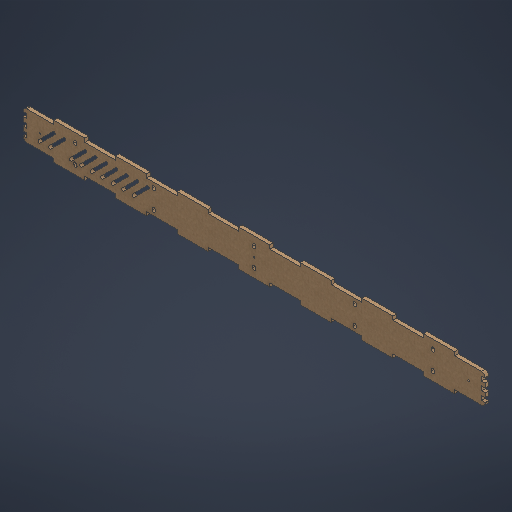
# Autodesk Inventor part: BaseBoxLengthFace
Saved by Autodesk Inventor 2027.1 (Build 311270010, 270A)
## iProperties
Created: 2026-10-13
Part Number: BaseBoxLengthFace
Material: MDF Medium Density Fiberboard
Document SubType Name: Modeling
Designer: SDS Scholar
Density: 0.8 g/cm^3
Appearance: Cardboard - Corrugated
Author: SDS Scholar
Autodesk Inventor part; units mm, degrees
ref_plane "YZ Plane" through (0, 0, 0) normal (1, 0, 0) x (0, 1, 0)
ref_plane "XZ Plane" through (0, 0, 0) normal (0, 1, 0) x (-1, 0, 0)
ref_plane "XY Plane" through (0, 0, 0) normal (0, 0, 1) x (1, 0, 0)
sketch "Sketch1" plane through (0, 0, 0) normal (0, 0, 1) x (1, 0, 0)
  line L0 (-442.5, 35) -> (442.5, 35)
  line L1 (442.5, 35) -> (442.5, -35)
  line L2 (442.5, -35) -> (-442.5, -35)
  line L3 (-442.5, -35) -> (-442.5, 35)
  point P0 (0, 0)
  point P1 (0, 35)
  point P2 (442.5, 0)
  dimension "d0" = 885
  dimension "d1" = 70
  constraints: 8 end point, 2 midpoint, 2 parallel, 1 horizontal, 1 horizontal alignment, 1 perpendicular, 1 vertical alignment
  measures "d0" distance of L0.start L0.end
  measures "d1" distance of L2.end L0.start
extrude "Extrusion1" add sketch "Sketch1" along normal blind 7
sketch "Sketch2" plane through (0, 0, 7) normal (0, 0, 1) x (1, 0, 0)
  line L0 (-383.3579, 14.1421) -> (-411.6421, -14.1421) construction
  line L1 (-385.1256, 15.9099) -> (-413.4099, -12.3744)
  line L2 (-409.8744, -15.9099) -> (-381.5901, 12.3744)
  arc A0 (-381.5901, 12.3744) -> (-385.1256, 15.9099) centre (-383.3579, 14.1421) ccw
  arc A1 (-413.4099, -12.3744) -> (-409.8744, -15.9099) centre (-411.6421, -14.1421) ccw
  line L3 (-397.5, 0) -> (-442.5, 0)
  line L4 (-442.5, 35) -> (-442.5, -35) projected
  point P0 (0, 0)
  dimension "d4" = 40
  dimension "d5" = 45
  dimension "d6" = 135
  dimension "d7" = 2.5
  constraints: 10 end point, 4 point on circle, 4 tangent, 2 centre point, 2 midpoint, 1 horizontal, 1 parallel
  measures "d4" distance of L0.start L0.end
  measures "d5" distance of L3.start L3.end
  measures "d6" angle of L3 L0
  measures "d7" radius of A1
extrude "Extrusion2" cut sketch "Sketch2" against normal through all
pattern_linear "Rectangular Pattern1" count 10 spacing 20 along (1, 0, 0) of "Extrusion2"
sketch "Sketch3" plane through (0, 0, 0) normal (0, 0, -1) x (-1, 0, 0)
  arc A0 (205.1256, 15.9099) -> (201.5901, 12.3744) centre (203.3579, 14.1421) ccw projected
  line L0 (205.1256, 15.9099) -> (233.4099, -12.3744) projected
  arc A1 (229.8744, -15.9099) -> (233.4099, -12.3744) centre (231.6421, -14.1421) ccw projected
  line L1 (229.8744, -15.9099) -> (201.5901, 12.3744) projected
  arc A2 (225.1256, 15.9099) -> (221.5901, 12.3744) centre (223.3579, 14.1421) ccw projected
  line L2 (225.1256, 15.9099) -> (253.4099, -12.3744) projected
  arc A3 (249.8744, -15.9099) -> (253.4099, -12.3744) centre (251.6421, -14.1421) ccw projected
  line L3 (249.8744, -15.9099) -> (221.5901, 12.3744) projected
  arc A4 (245.1256, 15.9099) -> (241.5901, 12.3744) centre (243.3579, 14.1421) ccw projected
  line L4 (245.1256, 15.9099) -> (273.4099, -12.3744) projected
  arc A5 (269.8744, -15.9099) -> (273.4099, -12.3744) centre (271.6421, -14.1421) ccw projected
  line L5 (269.8744, -15.9099) -> (241.5901, 12.3744) projected
  arc A6 (265.1256, 15.9099) -> (261.5901, 12.3744) centre (263.3579, 14.1421) ccw projected
  line L6 (265.1256, 15.9099) -> (293.4099, -12.3744) projected
  arc A7 (289.8744, -15.9099) -> (293.4099, -12.3744) centre (291.6421, -14.1421) ccw projected
  line L7 (289.8744, -15.9099) -> (261.5901, 12.3744) projected
  arc A8 (285.1256, 15.9099) -> (281.5901, 12.3744) centre (283.3579, 14.1421) ccw projected
  line L8 (285.1256, 15.9099) -> (313.4099, -12.3744) projected
  arc A9 (309.8744, -15.9099) -> (313.4099, -12.3744) centre (311.6421, -14.1421) ccw projected
  line L9 (309.8744, -15.9099) -> (281.5901, 12.3744) projected
  arc A10 (305.1256, 15.9099) -> (301.5901, 12.3744) centre (303.3579, 14.1421) ccw projected
  line L10 (305.1256, 15.9099) -> (333.4099, -12.3744) projected
  arc A11 (329.8744, -15.9099) -> (333.4099, -12.3744) centre (331.6421, -14.1421) ccw projected
  line L11 (329.8744, -15.9099) -> (301.5901, 12.3744) projected
  arc A12 (325.1256, 15.9099) -> (321.5901, 12.3744) centre (323.3579, 14.1421) ccw projected
  line L12 (325.1256, 15.9099) -> (353.4099, -12.3744) projected
  arc A13 (349.8744, -15.9099) -> (353.4099, -12.3744) centre (351.6421, -14.1421) ccw projected
  line L13 (349.8744, -15.9099) -> (321.5901, 12.3744) projected
  arc A14 (345.1256, 15.9099) -> (341.5901, 12.3744) centre (343.3579, 14.1421) ccw projected
  line L14 (345.1256, 15.9099) -> (373.4099, -12.3744) projected
  arc A15 (369.8744, -15.9099) -> (373.4099, -12.3744) centre (371.6421, -14.1421) ccw projected
  line L15 (369.8744, -15.9099) -> (341.5901, 12.3744) projected
  arc A16 (365.1256, 15.9099) -> (361.5901, 12.3744) centre (363.3579, 14.1421) ccw projected
  line L16 (365.1256, 15.9099) -> (393.4099, -12.3744) projected
  arc A17 (389.8744, -15.9099) -> (393.4099, -12.3744) centre (391.6421, -14.1421) ccw projected
  line L17 (389.8744, -15.9099) -> (361.5901, 12.3744) projected
  arc A18 (409.8744, -15.9099) -> (413.4099, -12.3744) centre (411.6421, -14.1421) ccw projected
  line L18 (409.8744, -15.9099) -> (381.5901, 12.3744) projected
  arc A19 (385.1256, 15.9099) -> (381.5901, 12.3744) centre (383.3579, 14.1421) ccw projected
  line L19 (385.1256, 15.9099) -> (413.4099, -12.3744) projected
  line L20 (442.5, -35) -> (-442.5, -35) projected
  line L21 (442.5, 35) -> (442.5, -35) projected
  line L22 (-442.5, 35) -> (442.5, 35) projected
  line L23 (-442.5, -35) -> (-442.5, 35) projected
  line L24 (435.5, 28) -> (435.5, -28)
  line L25 (435.5, -28) -> (-435.5, -28)
  line L26 (-435.5, -28) -> (-435.5, 28)
  line L27 (-435.5, 28) -> (435.5, 28)
  line L28 (-442.5, 35) -> (-383.725, 35)
  line L29 (-383.725, 35) -> (-383.725, 28)
  line L30 (-383.725, 28) -> (-442.5, 28)
  line L31 (-442.5, 28) -> (-442.5, 35)
  line L32 (-383.725, 35) -> (-324.275, 35)
  line L33 (-324.275, 35) -> (-324.275, 28)
  line L34 (-324.275, 28) -> (-383.725, 28)
  line L35 (-383.725, 28) -> (-383.725, 35)
  line L36 (-265.725, 35) -> (-265.725, 28)
  line L37 (-206.275, 35) -> (-206.275, 28)
  line L38 (-147.725, 35) -> (-147.725, 28)
  line L39 (-88.275, 35) -> (-88.275, 28)
  line L40 (-29.725, 35) -> (-29.725, 28)
  line L41 (29.725, 35) -> (29.725, 28)
  line L42 (88.275, 35) -> (88.275, 28)
  line L43 (147.725, 35) -> (147.725, 28)
  line L44 (206.275, 35) -> (206.275, 28)
  line L45 (265.725, 35) -> (265.725, 28)
  line L46 (324.275, 35) -> (324.275, 28)
  line L47 (383.725, 35) -> (383.725, 28)
  line L48 (0, 35) -> (0, -35) construction
  line L49 (-442.5, 0) -> (442.5, 0) construction
  line L50 (-383.725, -35) -> (-383.725, -28)
  line L51 (-324.275, -35) -> (-324.275, -28)
  line L52 (-265.725, -35) -> (-265.725, -28)
  line L53 (-206.275, -35) -> (-206.275, -28)
  line L54 (-147.725, -35) -> (-147.725, -28)
  line L55 (-88.275, -35) -> (-88.275, -28)
  line L56 (-29.725, -35) -> (-29.725, -28)
  line L57 (29.725, -35) -> (29.725, -28)
  line L58 (88.275, -35) -> (88.275, -28)
  line L59 (147.725, -35) -> (147.725, -28)
  line L60 (206.275, -35) -> (206.275, -28)
  line L61 (265.725, -35) -> (265.725, -28)
  line L62 (324.275, -35) -> (324.275, -28)
  line L63 (383.725, -35) -> (383.725, -28)
  line L64 (-442.5, 28) -> (-435.5, 28)
  line L65 (-435.5, 28) -> (-435.5, 20)
  line L66 (-435.5, 20) -> (-442.5, 20)
  line L67 (-442.5, 20) -> (-442.5, 28)
  line L68 (-442.5, 20) -> (-435.5, 20)
  line L69 (-435.5, 20) -> (-435.5, 12)
  line L70 (-435.5, 12) -> (-442.5, 12)
  line L71 (-442.5, 12) -> (-442.5, 20)
  line L72 (-442.5, 4) -> (-435.5, 4)
  line L73 (-435.5, -4) -> (-442.5, -4)
  line L74 (-442.5, 12) -> (-435.5, 12)
  line L75 (-442.5, -12) -> (-435.5, -12)
  line L76 (-435.5, -20) -> (-442.5, -20)
  line L77 (-442.5, -4) -> (-435.5, -4)
  line L78 (-435.5, -28) -> (-442.5, -28)
  line L79 (383.725, 28) -> (442.5, 28)
  line L80 (435.5, 20) -> (442.5, 20)
  line L81 (442.5, 4) -> (435.5, 4)
  line L82 (435.5, -4) -> (442.5, -4)
  line L83 (442.5, 12) -> (435.5, 12)
  line L84 (442.5, -12) -> (435.5, -12)
  line L85 (435.5, -20) -> (442.5, -20)
  line L86 (435.5, -28) -> (442.5, -28)
  point P0 (0, 0)
  point P1 (383.725, -28)
  point P2 (383.725, -35)
  point P3 (265.725, -28)
  point P4 (265.725, -35)
  point P5 (324.275, -35)
  point P6 (324.275, -28)
  point P7 (147.725, -28)
  point P8 (147.725, -35)
  point P9 (206.275, -35)
  point P10 (206.275, -28)
  point P11 (29.725, -28)
  point P12 (29.725, -35)
  point P13 (88.275, -35)
  point P14 (88.275, -28)
  point P15 (-88.275, -28)
  point P16 (-88.275, -35)
  point P17 (-29.725, -35)
  point P18 (-29.725, -28)
  point P19 (-206.275, -28)
  point P20 (-206.275, -35)
  point P21 (-147.725, -35)
  point P22 (-147.725, -28)
  point P23 (-324.275, -28)
  point P24 (-324.275, -35)
  point P25 (-265.725, -35)
  point P26 (-265.725, -28)
  point P27 (-383.725, -35)
  point P28 (-383.725, -28)
  point P29 (383.725, 28)
  point P30 (324.275, 28)
  point P31 (265.725, 28)
  point P32 (206.275, 28)
  point P33 (147.725, 28)
  point P34 (88.275, 28)
  point P35 (29.725, 28)
  point P36 (-29.725, 28)
  point P37 (-88.275, 28)
  point P38 (-147.725, 28)
  point P39 (-206.275, 28)
  point P40 (-265.725, 28)
  point P41 (435.5, 28)
  point P42 (435.5, 28)
  point P43 (-435.5, 28)
  dimension "d13" = 7
  dimension "d14" = 58.775
  dimension "d15" = 59.45
  dimension "d18" = 118
  dimension "d23" = 8
  dimension "d24" = 8
  dimension "d27" = 16
  constraints: 126 end point, 43 symmetric about line, 8 parallel, 5 horizontal, 5 perpendicular, 5 point on line, 4 midpoint, 1 vertical, 57 other
  measures "d13" distance between parallel lines of L22 L27
  measures "d14" distance between parallel lines of L23 L29
  measures "d15" distance between parallel lines of L33 L29
  measures "d18" distance of L28.end L36.start
  measures "d23" distance between parallel lines of L30 L66
  measures "d24" distance between parallel lines of L70 L66
  measures "d27" distance of L66.end L72.start
extrude "Extrusion3" cut sketch "Sketch3" against normal through all contours L20 L63 L25 L86 L21 | L20 L61 L25 L62 | L85 L24 L84 L21 | L20 L59 L25 L60 | L82 L24 L81 L21 | L20 L57 L25 L58 | L83 L24 L80 L21 | L20 L55 L25 L56 | L79 L27 L47 L22 L21 | L20 L53 L25 L54 | L46 L27 L45 L22 | L20 L51 L25 L52 | L44 L27 L43 L22 | L20 L23 L78 L25 L50 | L42 L27 L41 L22 | L23 L75 L26 L76 | L40 L27 L39 L22 | L23 L72 L26 L73 | L38 L27 L37 L22 | L23 L66 L26 L70 | L36 L27 L33 L22 | L23 L22 L29 L27 L30
fillet "Fillet2" radius 7 4 edges at (442.5, 28, 3.5) (442.5, -28, 3.5) (-442.5, 28, 3.5) (-442.5, -28, 3.5)
sketch "Sketch4" plane through (0, 0, 7) normal (0, 0, 1) x (1, 0, 0)
  arc A0 (-442.5, -21) -> (-435.5, -28) centre (-435.5, -21) ccw projected
  line L0 (-435.5, -28) -> (-383.725, -28) projected
  line L1 (-383.725, -28) -> (-383.725, -35) projected
  line L2 (-383.725, -35) -> (-324.275, -35) projected
  line L3 (-324.275, -35) -> (-324.275, -28) projected
  line L4 (-324.275, -28) -> (-265.725, -28) projected
  line L5 (-265.725, -28) -> (-265.725, -35) projected
  line L6 (-265.725, -35) -> (-206.275, -35) projected
  line L7 (-206.275, -35) -> (-206.275, -28) projected
  line L8 (-206.275, -28) -> (-147.725, -28) projected
  line L9 (-147.725, -28) -> (-147.725, -35) projected
  line L10 (-147.725, -35) -> (-88.275, -35) projected
  line L11 (-88.275, -35) -> (-88.275, -28) projected
  line L12 (-88.275, -28) -> (-29.725, -28) projected
  line L13 (-29.725, -28) -> (-29.725, -35) projected
  line L14 (-29.725, -35) -> (29.725, -35) projected
  line L15 (29.725, -35) -> (29.725, -28) projected
  line L16 (29.725, -28) -> (88.275, -28) projected
  line L17 (88.275, -28) -> (88.275, -35) projected
  line L18 (88.275, -35) -> (147.725, -35) projected
  line L19 (147.725, -35) -> (147.725, -28) projected
  line L20 (147.725, -28) -> (206.275, -28) projected
  line L21 (206.275, -28) -> (206.275, -35) projected
  line L22 (206.275, -35) -> (265.725, -35) projected
  line L23 (265.725, -35) -> (265.725, -28) projected
  line L24 (265.725, -28) -> (324.275, -28) projected
  line L25 (324.275, -28) -> (324.275, -35) projected
  line L26 (324.275, -35) -> (383.725, -35) projected
  line L27 (383.725, -35) -> (383.725, -28) projected
  line L28 (383.725, -28) -> (435.5, -28) projected
  arc A1 (435.5, -28) -> (442.5, -21) centre (435.5, -21) ccw projected
  line L29 (442.5, -21) -> (442.5, -20) projected
  line L30 (442.5, -20) -> (435.5, -20) projected
  line L31 (435.5, -20) -> (435.5, -12) projected
  line L32 (435.5, -12) -> (442.5, -12) projected
  line L33 (442.5, -12) -> (442.5, -4) projected
  line L34 (442.5, -4) -> (435.5, -4) projected
  line L35 (435.5, -4) -> (435.5, 4) projected
  line L36 (435.5, 4) -> (442.5, 4) projected
  line L37 (442.5, 4) -> (442.5, 12) projected
  line L38 (442.5, 12) -> (435.5, 12) projected
  line L39 (435.5, 12) -> (435.5, 20) projected
  line L40 (435.5, 20) -> (442.5, 20) projected
  line L41 (442.5, 20) -> (442.5, 21) projected
  arc A2 (442.5, 21) -> (435.5, 28) centre (435.5, 21) ccw projected
  line L42 (435.5, 28) -> (383.725, 28) projected
  line L43 (383.725, 28) -> (383.725, 35) projected
  line L44 (383.725, 35) -> (324.275, 35) projected
  line L45 (324.275, 35) -> (324.275, 28) projected
  line L46 (324.275, 28) -> (265.725, 28) projected
  line L47 (265.725, 28) -> (265.725, 35) projected
  line L48 (265.725, 35) -> (206.275, 35) projected
  line L49 (206.275, 35) -> (206.275, 28) projected
  line L50 (206.275, 28) -> (147.725, 28) projected
  line L51 (147.725, 28) -> (147.725, 35) projected
  line L52 (147.725, 35) -> (88.275, 35) projected
  line L53 (88.275, 35) -> (88.275, 28) projected
  line L54 (88.275, 28) -> (29.725, 28) projected
  line L55 (29.725, 28) -> (29.725, 35) projected
  line L56 (29.725, 35) -> (-29.725, 35) projected
  line L57 (-29.725, 35) -> (-29.725, 28) projected
  line L58 (-29.725, 28) -> (-88.275, 28) projected
  line L59 (-88.275, 28) -> (-88.275, 35) projected
  line L60 (-88.275, 35) -> (-147.725, 35) projected
  line L61 (-147.725, 35) -> (-147.725, 28) projected
  line L62 (-147.725, 28) -> (-206.275, 28) projected
  line L63 (-206.275, 28) -> (-206.275, 35) projected
  line L64 (-206.275, 35) -> (-265.725, 35) projected
  line L65 (-265.725, 35) -> (-265.725, 28) projected
  line L66 (-265.725, 28) -> (-324.275, 28) projected
  line L67 (-324.275, 28) -> (-324.275, 35) projected
  line L68 (-324.275, 35) -> (-383.725, 35) projected
  line L69 (-383.725, 35) -> (-383.725, 28) projected
  line L70 (-383.725, 28) -> (-435.5, 28) projected
  arc A3 (-435.5, 28) -> (-442.5, 21) centre (-435.5, 21) ccw projected
  line L71 (-442.5, 21) -> (-442.5, 20) projected
  line L72 (-442.5, 20) -> (-435.5, 20) projected
  line L73 (-435.5, 20) -> (-435.5, 12) projected
  line L74 (-435.5, 12) -> (-442.5, 12) projected
  line L75 (-442.5, 12) -> (-442.5, 4) projected
  line L76 (-442.5, 4) -> (-435.5, 4) projected
  line L77 (-435.5, 4) -> (-435.5, -4) projected
  line L78 (-435.5, -4) -> (-442.5, -4) projected
  line L79 (-442.5, -4) -> (-442.5, -12) projected
  line L80 (-442.5, -12) -> (-435.5, -12) projected
  line L81 (-435.5, -12) -> (-435.5, -20) projected
  line L82 (-435.5, -20) -> (-442.5, -20) projected
  line L83 (-442.5, -20) -> (-442.5, -21) projected
  arc A4 (-413.4099, -12.3744) -> (-409.8744, -15.9099) centre (-411.6421, -14.1421) ccw projected
  line L84 (-413.4099, -12.3744) -> (-385.1256, 15.9099) projected
  arc A5 (-381.5901, 12.3744) -> (-385.1256, 15.9099) centre (-383.3579, 14.1421) ccw projected
  line L85 (-381.5901, 12.3744) -> (-409.8744, -15.9099) projected
  arc A6 (-361.5901, 12.3744) -> (-365.1256, 15.9099) centre (-363.3579, 14.1421) ccw projected
  line L86 (-361.5901, 12.3744) -> (-389.8744, -15.9099) projected
  arc A7 (-393.4099, -12.3744) -> (-389.8744, -15.9099) centre (-391.6421, -14.1421) ccw projected
  line L87 (-393.4099, -12.3744) -> (-365.1256, 15.9099) projected
  arc A8 (-341.5901, 12.3744) -> (-345.1256, 15.9099) centre (-343.3579, 14.1421) ccw projected
  line L88 (-341.5901, 12.3744) -> (-369.8744, -15.9099) projected
  arc A9 (-373.4099, -12.3744) -> (-369.8744, -15.9099) centre (-371.6421, -14.1421) ccw projected
  line L89 (-373.4099, -12.3744) -> (-345.1256, 15.9099) projected
  arc A10 (-321.5901, 12.3744) -> (-325.1256, 15.9099) centre (-323.3579, 14.1421) ccw projected
  line L90 (-321.5901, 12.3744) -> (-349.8744, -15.9099) projected
  arc A11 (-353.4099, -12.3744) -> (-349.8744, -15.9099) centre (-351.6421, -14.1421) ccw projected
  line L91 (-353.4099, -12.3744) -> (-325.1256, 15.9099) projected
  arc A12 (-301.5901, 12.3744) -> (-305.1256, 15.9099) centre (-303.3579, 14.1421) ccw projected
  line L92 (-301.5901, 12.3744) -> (-329.8744, -15.9099) projected
  arc A13 (-333.4099, -12.3744) -> (-329.8744, -15.9099) centre (-331.6421, -14.1421) ccw projected
  line L93 (-333.4099, -12.3744) -> (-305.1256, 15.9099) projected
  arc A14 (-281.5901, 12.3744) -> (-285.1256, 15.9099) centre (-283.3579, 14.1421) ccw projected
  line L94 (-281.5901, 12.3744) -> (-309.8744, -15.9099) projected
  arc A15 (-313.4099, -12.3744) -> (-309.8744, -15.9099) centre (-311.6421, -14.1421) ccw projected
  line L95 (-313.4099, -12.3744) -> (-285.1256, 15.9099) projected
  arc A16 (-261.5901, 12.3744) -> (-265.1256, 15.9099) centre (-263.3579, 14.1421) ccw projected
  line L96 (-261.5901, 12.3744) -> (-289.8744, -15.9099) projected
  arc A17 (-293.4099, -12.3744) -> (-289.8744, -15.9099) centre (-291.6421, -14.1421) ccw projected
  line L97 (-293.4099, -12.3744) -> (-265.1256, 15.9099) projected
  arc A18 (-241.5901, 12.3744) -> (-245.1256, 15.9099) centre (-243.3579, 14.1421) ccw projected
  line L98 (-241.5901, 12.3744) -> (-269.8744, -15.9099) projected
  arc A19 (-273.4099, -12.3744) -> (-269.8744, -15.9099) centre (-271.6421, -14.1421) ccw projected
  line L99 (-273.4099, -12.3744) -> (-245.1256, 15.9099) projected
  arc A20 (-221.5901, 12.3744) -> (-225.1256, 15.9099) centre (-223.3579, 14.1421) ccw projected
  line L100 (-221.5901, 12.3744) -> (-249.8744, -15.9099) projected
  arc A21 (-253.4099, -12.3744) -> (-249.8744, -15.9099) centre (-251.6421, -14.1421) ccw projected
  line L101 (-253.4099, -12.3744) -> (-225.1256, 15.9099) projected
  arc A22 (-201.5901, 12.3744) -> (-205.1256, 15.9099) centre (-203.3579, 14.1421) ccw projected
  line L102 (-201.5901, 12.3744) -> (-229.8744, -15.9099) projected
  arc A23 (-233.4099, -12.3744) -> (-229.8744, -15.9099) centre (-231.6421, -14.1421) ccw projected
  line L103 (-233.4099, -12.3744) -> (-205.1256, 15.9099) projected
  line L104 (0, 35) -> (0, -35) construction
  line L105 (-435.5, 0) -> (435.5, 0) construction
  line L106 (342.5, 19.5) -> (342.5, 16.5) construction
  line L107 (339.6, 19.5) -> (339.6, 16.5)
  line L108 (345.4, 16.5) -> (345.4, 19.5)
  arc A24 (345.4, 19.5) -> (339.6, 19.5) centre (342.5, 19.5) ccw
  arc A25 (339.6, 16.5) -> (345.4, 16.5) centre (342.5, 16.5) ccw
  line L109 (192.5, 19.5) -> (192.5, 16.5) construction
  line L110 (189.6, 19.5) -> (189.6, 16.5)
  line L111 (195.4, 16.5) -> (195.4, 19.5)
  arc A26 (195.4, 19.5) -> (189.6, 19.5) centre (192.5, 19.5) ccw
  arc A27 (189.6, 16.5) -> (195.4, 16.5) centre (192.5, 16.5) ccw
  line L112 (2.9, 16.5) -> (2.9, 19.5)
  line L113 (0, 19.5) -> (0, 16.5) construction
  arc A28 (-2.9, 16.5) -> (2.9, 16.5) centre (0, 16.5) ccw
  line L114 (-2.9, 19.5) -> (-2.9, 16.5)
  arc A29 (2.9, 19.5) -> (-2.9, 19.5) centre (0, 19.5) ccw
  line L115 (-342.5, 19.5) -> (-342.5, 16.5) construction
  line L116 (-339.6, 19.5) -> (-339.6, 16.5)
  line L117 (-345.4, 16.5) -> (-345.4, 19.5)
  arc A30 (-339.6, 19.5) -> (-345.4, 19.5) centre (-342.5, 19.5) ccw
  arc A31 (-345.4, 16.5) -> (-339.6, 16.5) centre (-342.5, 16.5) ccw
  line L118 (-195.4, 16.5) -> (-195.4, 19.5)
  line L119 (-192.5, 19.5) -> (-192.5, 16.5) construction
  arc A32 (-195.4, 16.5) -> (-189.6, 16.5) centre (-192.5, 16.5) ccw
  line L120 (-189.6, 19.5) -> (-189.6, 16.5)
  arc A33 (-189.6, 19.5) -> (-195.4, 19.5) centre (-192.5, 19.5) ccw
  line L121 (342.5, -19.5) -> (342.5, -16.5) construction
  line L122 (339.6, -19.5) -> (339.6, -16.5)
  line L123 (345.4, -16.5) -> (345.4, -19.5)
  arc A34 (339.6, -19.5) -> (345.4, -19.5) centre (342.5, -19.5) ccw
  arc A35 (345.4, -16.5) -> (339.6, -16.5) centre (342.5, -16.5) ccw
  line L124 (195.4, -16.5) -> (195.4, -19.5)
  line L125 (192.5, -19.5) -> (192.5, -16.5) construction
  arc A36 (195.4, -16.5) -> (189.6, -16.5) centre (192.5, -16.5) ccw
  line L126 (189.6, -19.5) -> (189.6, -16.5)
  arc A37 (189.6, -19.5) -> (195.4, -19.5) centre (192.5, -19.5) ccw
  line L127 (-2.9, -19.5) -> (-2.9, -16.5)
  arc A38 (2.9, -16.5) -> (-2.9, -16.5) centre (0, -16.5) ccw
  line L128 (0, -19.5) -> (0, -16.5) construction
  line L129 (2.9, -16.5) -> (2.9, -19.5)
  arc A39 (-2.9, -19.5) -> (2.9, -19.5) centre (0, -19.5) ccw
  line L130 (-189.6, -19.5) -> (-189.6, -16.5)
  line L131 (-192.5, -19.5) -> (-192.5, -16.5) construction
  arc A40 (-189.6, -16.5) -> (-195.4, -16.5) centre (-192.5, -16.5) ccw
  arc A41 (-195.4, -19.5) -> (-189.6, -19.5) centre (-192.5, -19.5) ccw
  line L132 (-195.4, -16.5) -> (-195.4, -19.5)
  line L133 (-339.6, -19.5) -> (-339.6, -16.5)
  line L134 (-342.5, -19.5) -> (-342.5, -16.5) construction
  arc A42 (-339.6, -16.5) -> (-345.4, -16.5) centre (-342.5, -16.5) ccw
  arc A43 (-345.4, -19.5) -> (-339.6, -19.5) centre (-342.5, -19.5) ccw
  line L135 (-345.4, -16.5) -> (-345.4, -19.5)
  point P0 (0, 0)
  point P1 (342.5, 18)
  point P2 (0, 18)
  point P3 (192.5, 18)
  point P4 (0, 0)
  point P5 (-342.5, 18)
  point P6 (-192.5, 18)
  point P7 (-345.1256, -15.9099)
  point P8 (-343.3579, -14.1421)
  point P9 (342.5, -18)
  point P10 (0, -18)
  point P11 (192.5, -18)
  point P12 (-192.5, -18)
  point P13 (-342.5, -18)
  dimension "d36" = 3
  dimension "d37" = 5.8
  dimension "d38" = 8.5
  dimension "d39" = 100
  dimension "d40" = 3
  dimension "d41" = 5.8
  dimension "d42" = 150
  dimension "d43" = 8.5
  dimension "d44" = 3
  dimension "d45" = 5.8
  constraints: 84 end point, 51 symmetric about line, 40 point on circle, 20 centre point, 12 tangent, 8 midpoint, 3 parallel, 3 vertical, 1 horizontal alignment, 1 vertical alignment, 14 other
  measures "d36" distance of L106.start L106.end
  measures "d37" diameter of A25
  measures "d38" distance from line of L46 L106.start
  measures "d39" distance between parallel lines of L37 L106
  measures "d40" distance of L109.start L109.end
  measures "d41" diameter of A27
  measures "d42" distance between parallel lines of L106 L109
  measures "d43" distance from line of L50 L109.start
  measures "d44" distance of L113.start L113.end
  measures "d45" diameter of A28
sketch "Sketch5" plane through (0, 0, 7) normal (0, 0, 1) x (1, 0, 0)
  arc A0 (-442.5, -21) -> (-435.5, -28) centre (-435.5, -21) ccw projected
  line L0 (-435.5, -28) -> (-383.725, -28) projected
  line L1 (-383.725, -28) -> (-383.725, -35) projected
  line L2 (-383.725, -35) -> (-324.275, -35) projected
  line L3 (-324.275, -35) -> (-324.275, -28) projected
  line L4 (-324.275, -28) -> (-265.725, -28) projected
  line L5 (-265.725, -28) -> (-265.725, -35) projected
  line L6 (-265.725, -35) -> (-206.275, -35) projected
  line L7 (-206.275, -35) -> (-206.275, -28) projected
  line L8 (-206.275, -28) -> (-147.725, -28) projected
  line L9 (-147.725, -28) -> (-147.725, -35) projected
  line L10 (-147.725, -35) -> (-88.275, -35) projected
  line L11 (-88.275, -35) -> (-88.275, -28) projected
  line L12 (-88.275, -28) -> (-29.725, -28) projected
  line L13 (-29.725, -28) -> (-29.725, -35) projected
  line L14 (-29.725, -35) -> (29.725, -35) projected
  line L15 (29.725, -35) -> (29.725, -28) projected
  line L16 (29.725, -28) -> (88.275, -28) projected
  line L17 (88.275, -28) -> (88.275, -35) projected
  line L18 (88.275, -35) -> (147.725, -35) projected
  line L19 (147.725, -35) -> (147.725, -28) projected
  line L20 (147.725, -28) -> (206.275, -28) projected
  line L21 (206.275, -28) -> (206.275, -35) projected
  line L22 (206.275, -35) -> (265.725, -35) projected
  line L23 (265.725, -35) -> (265.725, -28) projected
  line L24 (265.725, -28) -> (324.275, -28) projected
  line L25 (324.275, -28) -> (324.275, -35) projected
  line L26 (324.275, -35) -> (383.725, -35) projected
  line L27 (383.725, -35) -> (383.725, -28) projected
  line L28 (383.725, -28) -> (435.5, -28) projected
  arc A1 (435.5, -28) -> (442.5, -21) centre (435.5, -21) ccw projected
  line L29 (442.5, -21) -> (442.5, -20) projected
  line L30 (442.5, -20) -> (435.5, -20) projected
  line L31 (435.5, -20) -> (435.5, -12) projected
  line L32 (435.5, -12) -> (442.5, -12) projected
  line L33 (442.5, -12) -> (442.5, -4) projected
  line L34 (442.5, -4) -> (435.5, -4) projected
  line L35 (435.5, -4) -> (435.5, 4) projected
  line L36 (435.5, 4) -> (442.5, 4) projected
  line L37 (442.5, 4) -> (442.5, 12) projected
  line L38 (442.5, 12) -> (435.5, 12) projected
  line L39 (435.5, 12) -> (435.5, 20) projected
  line L40 (435.5, 20) -> (442.5, 20) projected
  line L41 (442.5, 20) -> (442.5, 21) projected
  arc A2 (442.5, 21) -> (435.5, 28) centre (435.5, 21) ccw projected
  line L42 (435.5, 28) -> (383.725, 28) projected
  line L43 (383.725, 28) -> (383.725, 35) projected
  line L44 (383.725, 35) -> (324.275, 35) projected
  line L45 (324.275, 35) -> (324.275, 28) projected
  line L46 (324.275, 28) -> (265.725, 28) projected
  line L47 (265.725, 28) -> (265.725, 35) projected
  line L48 (265.725, 35) -> (206.275, 35) projected
  line L49 (206.275, 35) -> (206.275, 28) projected
  line L50 (206.275, 28) -> (147.725, 28) projected
  line L51 (147.725, 28) -> (147.725, 35) projected
  line L52 (147.725, 35) -> (88.275, 35) projected
  line L53 (88.275, 35) -> (88.275, 28) projected
  line L54 (88.275, 28) -> (29.725, 28) projected
  line L55 (29.725, 28) -> (29.725, 35) projected
  line L56 (29.725, 35) -> (-29.725, 35) projected
  line L57 (-29.725, 35) -> (-29.725, 28) projected
  line L58 (-29.725, 28) -> (-88.275, 28) projected
  line L59 (-88.275, 28) -> (-88.275, 35) projected
  line L60 (-88.275, 35) -> (-147.725, 35) projected
  line L61 (-147.725, 35) -> (-147.725, 28) projected
  line L62 (-147.725, 28) -> (-206.275, 28) projected
  line L63 (-206.275, 28) -> (-206.275, 35) projected
  line L64 (-206.275, 35) -> (-265.725, 35) projected
  line L65 (-265.725, 35) -> (-265.725, 28) projected
  line L66 (-265.725, 28) -> (-324.275, 28) projected
  line L67 (-324.275, 28) -> (-324.275, 35) projected
  line L68 (-324.275, 35) -> (-383.725, 35) projected
  line L69 (-383.725, 35) -> (-383.725, 28) projected
  line L70 (-383.725, 28) -> (-435.5, 28) projected
  arc A3 (-435.5, 28) -> (-442.5, 21) centre (-435.5, 21) ccw projected
  line L71 (-442.5, 21) -> (-442.5, 20) projected
  line L72 (-442.5, 20) -> (-435.5, 20) projected
  line L73 (-435.5, 20) -> (-435.5, 12) projected
  line L74 (-435.5, 12) -> (-442.5, 12) projected
  line L75 (-442.5, 12) -> (-442.5, 4) projected
  line L76 (-442.5, 4) -> (-435.5, 4) projected
  line L77 (-435.5, 4) -> (-435.5, -4) projected
  line L78 (-435.5, -4) -> (-442.5, -4) projected
  line L79 (-442.5, -4) -> (-442.5, -12) projected
  line L80 (-442.5, -12) -> (-435.5, -12) projected
  line L81 (-435.5, -12) -> (-435.5, -20) projected
  line L82 (-435.5, -20) -> (-442.5, -20) projected
  line L83 (-442.5, -20) -> (-442.5, -21) projected
  arc A4 (-413.4099, -12.3744) -> (-409.8744, -15.9099) centre (-411.6421, -14.1421) ccw projected
  line L84 (-413.4099, -12.3744) -> (-385.1256, 15.9099) projected
  arc A5 (-381.5901, 12.3744) -> (-385.1256, 15.9099) centre (-383.3579, 14.1421) ccw projected
  line L85 (-381.5901, 12.3744) -> (-409.8744, -15.9099) projected
  arc A6 (-361.5901, 12.3744) -> (-365.1256, 15.9099) centre (-363.3579, 14.1421) ccw projected
  line L86 (-361.5901, 12.3744) -> (-389.8744, -15.9099) projected
  arc A7 (-393.4099, -12.3744) -> (-389.8744, -15.9099) centre (-391.6421, -14.1421) ccw projected
  line L87 (-393.4099, -12.3744) -> (-365.1256, 15.9099) projected
  arc A8 (-341.5901, 12.3744) -> (-345.1256, 15.9099) centre (-343.3579, 14.1421) ccw projected
  line L88 (-341.5901, 12.3744) -> (-369.8744, -15.9099) projected
  arc A9 (-373.4099, -12.3744) -> (-369.8744, -15.9099) centre (-371.6421, -14.1421) ccw projected
  line L89 (-373.4099, -12.3744) -> (-345.1256, 15.9099) projected
  arc A10 (-321.5901, 12.3744) -> (-325.1256, 15.9099) centre (-323.3579, 14.1421) ccw projected
  line L90 (-321.5901, 12.3744) -> (-349.8744, -15.9099) projected
  arc A11 (-353.4099, -12.3744) -> (-349.8744, -15.9099) centre (-351.6421, -14.1421) ccw projected
  line L91 (-353.4099, -12.3744) -> (-325.1256, 15.9099) projected
  arc A12 (-301.5901, 12.3744) -> (-305.1256, 15.9099) centre (-303.3579, 14.1421) ccw projected
  line L92 (-301.5901, 12.3744) -> (-329.8744, -15.9099) projected
  arc A13 (-333.4099, -12.3744) -> (-329.8744, -15.9099) centre (-331.6421, -14.1421) ccw projected
  line L93 (-333.4099, -12.3744) -> (-305.1256, 15.9099) projected
  arc A14 (-281.5901, 12.3744) -> (-285.1256, 15.9099) centre (-283.3579, 14.1421) ccw projected
  line L94 (-281.5901, 12.3744) -> (-309.8744, -15.9099) projected
  arc A15 (-313.4099, -12.3744) -> (-309.8744, -15.9099) centre (-311.6421, -14.1421) ccw projected
  line L95 (-313.4099, -12.3744) -> (-285.1256, 15.9099) projected
  arc A16 (-261.5901, 12.3744) -> (-265.1256, 15.9099) centre (-263.3579, 14.1421) ccw projected
  line L96 (-261.5901, 12.3744) -> (-289.8744, -15.9099) projected
  arc A17 (-293.4099, -12.3744) -> (-289.8744, -15.9099) centre (-291.6421, -14.1421) ccw projected
  line L97 (-293.4099, -12.3744) -> (-265.1256, 15.9099) projected
  arc A18 (-241.5901, 12.3744) -> (-245.1256, 15.9099) centre (-243.3579, 14.1421) ccw projected
  line L98 (-241.5901, 12.3744) -> (-269.8744, -15.9099) projected
  arc A19 (-273.4099, -12.3744) -> (-269.8744, -15.9099) centre (-271.6421, -14.1421) ccw projected
  line L99 (-273.4099, -12.3744) -> (-245.1256, 15.9099) projected
  arc A20 (-221.5901, 12.3744) -> (-225.1256, 15.9099) centre (-223.3579, 14.1421) ccw projected
  line L100 (-221.5901, 12.3744) -> (-249.8744, -15.9099) projected
  arc A21 (-253.4099, -12.3744) -> (-249.8744, -15.9099) centre (-251.6421, -14.1421) ccw projected
  line L101 (-253.4099, -12.3744) -> (-225.1256, 15.9099) projected
  arc A22 (-201.5901, 12.3744) -> (-205.1256, 15.9099) centre (-203.3579, 14.1421) ccw projected
  line L102 (-201.5901, 12.3744) -> (-229.8744, -15.9099) projected
  arc A23 (-233.4099, -12.3744) -> (-229.8744, -15.9099) centre (-231.6421, -14.1421) ccw projected
  line L103 (-233.4099, -12.3744) -> (-205.1256, 15.9099) projected
  point P0 (0, 0)
extrude "Extrusion4" add sketch "Sketch5" against normal blind 7 contours L88 A9 L89 A8
extrude "Extrusion5" cut sketch "Sketch4" against normal through all contours A31 L89 A8 | A8 L89 A31 L117 A30 L116 | A24 L108 A25 L107 | A26 L111 A27 L110 | A28 L114 A29 L112 | L118 A33 L120 A32 | L122 A35 L123 A34 | L124 A37 L126 A36 | L127 A38 L129 A39 | A41 L132 A40 L130 | A43 L135 A42 L133
sketch "Sketch6" plane through (0, 0, 7) normal (0, 0, 1) x (1, 0, 0)
  circle A0 centre (0, 0) radius 1.5
  circle A1 centre (410.5, 0) radius 1.5
  circle A2 centre (-410.5, 0) radius 1.5
  line L0 (-435.5, 4) -> (-435.5, -4) projected
  line L1 (435.5, -4) -> (435.5, 4) projected
  point P0 (-435.5, 0)
  point P1 (-435.5, 0)
  point P2 (-435.5, 0)
  point P3 (435.5, 0)
  dimension "d50" = 3
  dimension "d51" = 3
  dimension "d52" = 25
  dimension "d53" = 3
  dimension "d54" = 25
  constraints: 4 horizontal alignment, 4 midpoint, 3 centre point, 1 coincident
  measures "d50" diameter of A0
  measures "d51" diameter of A1
  measures "d52" distance from line of L0 A2.centre
  measures "d53" diameter of A2
  measures "d54" distance from line of L1 A1.centre
extrude "Extrusion6" cut sketch "Sketch6" against normal through all
sketch "Sketch7" plane through (0, 0, 0) normal (0, 0, -1) x (-1, 0, 0)
  point P0 (0, 0)
equation "\"d0\" = BaseTotalLength"
equation "\"d1\" = BaseHeight"
equation "\"d2\" = BaseWoodThickness"
equation "\"d13\" = BaseWoodThickness"
equation "\"GridProcutClearance\" = 5"
equation "\"GridBorderThickness\" = 5"
equation "\"GridBorderFillets\" = 7"
equation "\"GridTotalSize\" = 65"
equation "\"GridRobotClearance\" = 65"
equation "\"AluminiumExtrusionClearance\" = 35"
equation "\"BaseTotalLength\" = 885"
equation "\"WorkspaceLength\" = 515"
equation "\"WorkspaceHeight\" = 183"
equation "\"AxesBaseFillet\" = 15"
equation "\"Zaxis\" = 197"
equation "\"ProductTotalHeight\" = 45"
equation "\"VerticalStroke\" = 105"
equation "\"BackArea\" = 165"
equation "\"CylinderStroke\" = 75"
equation "\"BaseHeight\" = 70"
equation "\"BoxesWidth\" = 125"
equation "\"BaseWoodThickness\" = 7"
equation "\"kerf\" = 1.5"
equation "\"Kerf\" = 0.3"
equation "\"RxThickness\" = 1.8"
equation "\"support_2\" = 265"
body "Solid1"
